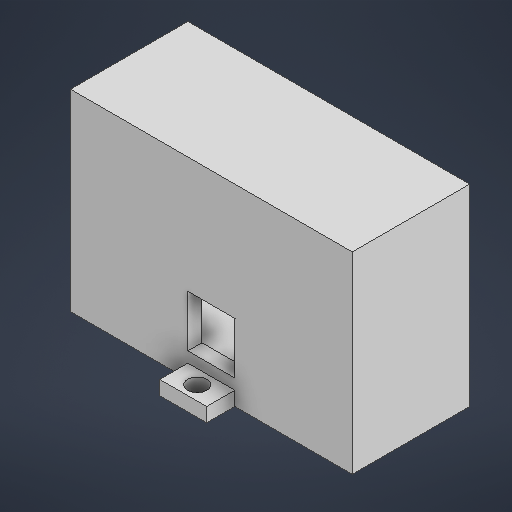
# Autodesk Inventor part: US_sensor_mount_back
Saved by Autodesk Inventor 2026.3 (Build 303398000, 398)
## iProperties
Created: 2026-09-23
Part Number: US_sensor_mount_back
Material: Generic
Document SubType Name: Modeling
Designer: grady
Density: 1 g/cm^3
Appearance: Default
Author: grady
Autodesk Inventor part; units mm, degrees
ref_plane "YZ Plane" through (0, 0, 0) normal (1, 0, 0) x (0, 1, 0)
ref_plane "XZ Plane" through (0, 0, 0) normal (0, 1, 0) x (-1, 0, 0)
ref_plane "XY Plane" through (0, 0, 0) normal (0, 0, 1) x (1, 0, 0)
sketch "Sketch1" plane through (0, 0, 0) normal (0, 0, 1) x (1, 0, 0)
  line L0 (0, 0) -> (60, 0)
  line L1 (60, 0) -> (60, 41)
  line L2 (60, 41) -> (0, 41)
  line L3 (0, 41) -> (0, 0)
  dimension "d0" = 60
  dimension "d1" = 41
  constraints: 8 end point, 2 parallel, 1 horizontal, 1 perpendicular
  measures "d0" distance of L2.end L1.end
  measures "d1" distance of L1.end L0.end
extrude "Extrusion1" add sketch "Sketch1" along normal blind 25
sketch "Sketch2" plane through (0, 0, 0) normal (0, 0, -1) x (-1, 0, 0)
  line L0 (0, 0) -> (-60, 0) projected
  line L1 (0, 0) -> (0, 5)
  line L2 (0, 41) -> (0, 0) projected
  line L3 (0, 5) -> (-5, 5)
  line L4 (-60, 0) -> (-60, 41) projected
  line L5 (-60, 41) -> (-55, 41)
  line L6 (-60, 41) -> (0, 41) projected
  line L7 (-55, 41) -> (-55, 36)
  line L8 (-55, 36) -> (-5, 36)
  line L9 (-5, 36) -> (-5, 5)
  line L10 (-5, 5) -> (-55, 5)
  line L11 (-55, 5) -> (-55, 36)
  dimension "d4" = 5
  dimension "d5" = 5
  dimension "d6" = 5
  dimension "d7" = 5
  constraints: 16 end point, 3 perpendicular, 2 parallel, 2 point on line, 1 horizontal
  measures "d4" distance of L0.start L1.end
  measures "d5" distance of L1.end L3.end
  measures "d6" distance of L4.end L5.end
  measures "d7" distance of L5.end L7.end
extrude "Extrusion2" cut sketch "Sketch2" against normal blind 22 contours L10 L11 L8 L9
sketch "Sketch3" plane through (0, 0, 0) normal (0, 0, -1) x (-1, 0, 0)
  line L0 (-5, 5) -> (-55, 5) projected
  line L1 (-5, 36) -> (-5, 5) projected
  line L2 (-55, 36) -> (-5, 36) projected
  point P0 (0, 0)
  point P1 (-57.5, 2.5)
  point P2 (-57.5, 38.5)
  point P3 (-2.5, 38.5)
  point P4 (-2.5, 2.5)
hole "Hole1" at (57.5, 2.5, 0) at (57.5, 38.5, 0) at (2.5, 38.5, 0) at (2.5, 2.5, 0) direction (0, 0, 1) diameter 3.2 depth 5 tip angle 118
sketch "Sketch4" plane through (0, 0, 25) normal (0, 0, 1) x (1, 0, 0)
  line L0 (5, 5) -> (55, 5) projected
  line L1 (25, 5.25) -> (35, 5.25)
  line L2 (35, 5.25) -> (35, 16.25)
  line L3 (35, 16.25) -> (25, 16.25)
  line L4 (25, 16.25) -> (25, 5.25)
  point P0 (0, 0)
  dimension "d25" = 10
  dimension "d26" = 11
  constraints: 8 end point, 2 parallel, 1 horizontal, 1 perpendicular
  measures "d25" distance of L3.end L2.end
  measures "d26" distance of L2.end L1.end
extrude "Extrusion3" cut sketch "Sketch4" against normal blind 3
sketch "Sketch5" plane through (0, 0, 25) normal (0, 0, 1) x (1, 0, 0)
  line L0 (25, 16.25) -> (25, 5.25) projected
  line L1 (25, 0) -> (35, 0)
  line L2 (0, 0) -> (60, 0) projected
  line L3 (35, 0) -> (35, 3)
  line L4 (35, 3) -> (25, 3)
  line L5 (25, 3) -> (25, 0)
  dimension "d30" = 10
  dimension "d31" = 3
  dimension "d32" = 10
  constraints: 8 end point, 1 perpendicular, 1 point on line, 1 vertical
  measures "d30" distance of L1.start L1.end
  measures "d31" distance of L1.end L3.end
  measures "d32" distance of L3.end L4.end
extrude "Extrusion4" add sketch "Sketch5" along normal blind 6
sketch "Sketch6" plane through (25, 3, 25) normal (0, 1, 0) x (1, 0, 0)
  line L0 (0, -6) -> (10, -6) projected
  line L1 (5, -6) -> (5, -3)
  point P0 (-25, 25)
  dimension "d35" = 3
  constraints: 2 end point, 1 coincident, 1 midpoint, 1 vertical
  measures "d35" distance of L1.start L1.end
hole "Hole2" at (30, 3, 28) direction (0, -1, 0) diameter 4.1 depth 5 tip angle 118
body "Solid1"
